Autodesk Fusion 360 part; units mm, degrees
(part 23 of 28)
  line L985 (32.9251, 30.277, -1.4859) -> (33.0999, 30.1879, -1.4859)
  line L986 (33.0999, 30.1879, -1.4859) -> (33.2586, 30.0726, -1.4859)
  line L987 (33.2586, 30.0726, -1.4859) -> (33.3973, 29.9339, -1.4859)
  line L988 (33.3973, 29.9339, -1.4859) -> (33.5126, 29.7752, -1.4859)
  line L989 (33.5126, 29.7752, -1.4859) -> (33.6016, 29.6005, -1.4859)
  line L990 (33.6016, 29.6005, -1.4859) -> (33.6622, 29.4139, -1.4859)
  line L991 (33.6622, 29.4139, -1.4859) -> (33.6929, 29.2202, -1.4859)
  line L992 (33.6929, 29.2202, -1.4859) -> (33.6968, 29.1221, -1.4859)
  line L993 (33.6968, 29.1221, -1.4859) -> (33.6968, 28.6221, -1.4859)
  line L994 (33.6968, 28.6221, -1.4859) -> (33.6929, 28.524, -1.4859)
  line L995 (33.6929, 28.524, -1.4859) -> (33.6622, 28.3303, -1.4859)
  line L996 (33.6622, 28.3303, -1.4859) -> (33.6016, 28.1438, -1.4859)
  line L997 (33.6016, 28.1438, -1.4859) -> (33.5126, 27.969, -1.4859)
  line L998 (33.5126, 27.969, -1.4859) -> (33.3973, 27.8103, -1.4859)
  line L999 (33.3973, 27.8103, -1.4859) -> (33.2586, 27.6716, -1.4859)
  line L1000 (33.2586, 27.6716, -1.4859) -> (33.0999, 27.5563, -1.4859)
  line L1001 (33.0999, 27.5563, -1.4859) -> (32.9251, 27.4673, -1.4859)
  line L1002 (32.9251, 27.4673, -1.4859) -> (32.7386, 27.4067, -1.4859)
  line L1003 (32.7386, 27.4067, -1.4859) -> (32.5448, 27.376, -1.4859)
  line L1004 (32.5448, 27.376, -1.4859) -> (32.3487, 27.376, -1.4859)
  line L1005 (32.3487, 27.376, -1.4859) -> (32.155, 27.4066, -1.4859)
  line L1006 (32.155, 27.4066, -1.4859) -> (31.9684, 27.4673, -1.4859)
  line L1007 (31.9684, 27.4673, -1.4859) -> (31.7936, 27.5563, -1.4859)
  line L1008 (31.7936, 27.5563, -1.4859) -> (31.635, 27.6716, -1.4859)
  line L1009 (31.635, 27.6716, -1.4859) -> (31.4963, 27.8103, -1.4859)
  line L1010 (31.4963, 27.8103, -1.4859) -> (31.381, 27.969, -1.4859)
  line L1011 (31.381, 27.969, -1.4859) -> (31.2919, 28.1438, -1.4859)
  line L1012 (31.2919, 28.1438, -1.4859) -> (31.2313, 28.3303, -1.4859)
  line L1013 (31.2313, 28.3303, -1.4859) -> (31.2006, 28.524, -1.4859)
  line L1014 (31.2006, 28.524, -1.4859) -> (31.1968, 28.6221, -1.4859)
  line L1015 (31.1968, 28.6221, -1.4859) -> (31.1968, 29.1221, -1.4859)
  line L1016 (31.1968, 29.1221, -1.4859) -> (31.2006, 29.2202, -1.4859)
  line L1017 (31.2006, 29.2202, -1.4859) -> (31.2313, 29.4139, -1.4859)
  line L1018 (31.2313, 29.4139, -1.4859) -> (31.2919, 29.6005, -1.4859)
  line L1019 (31.2919, 29.6005, -1.4859) -> (31.381, 29.7752, -1.4859)
  line L1020 (31.381, 29.7752, -1.4859) -> (31.4963, 29.9339, -1.4859)
  line L1021 (31.4963, 29.9339, -1.4859) -> (31.635, 30.0726, -1.4859)
  line L1022 (31.635, 30.0726, -1.4859) -> (31.7936, 30.1879, -1.4859)
  line L1023 (31.7936, 30.1879, -1.4859) -> (31.9684, 30.277, -1.4859)
  line L1024 (31.9684, 30.277, -1.4859) -> (32.155, 30.3376, -1.4859)
  line L1025 (32.155, 30.3376, -1.4859) -> (32.3487, 30.3683, -1.4859)
  line L1026 (32.3487, 30.3683, -1.4859) -> (32.5448, 30.3683, -1.4859)
  line L1027 (32.5448, 30.3683, -1.4859) -> (32.7386, 30.3376, -1.4859)
  line L1028 (93.6986, 30.3376, -1.4859) -> (93.8851, 30.277, -1.4859)
  line L1029 (93.8851, 30.277, -1.4859) -> (94.0599, 30.1879, -1.4859)
  line L1030 (94.0599, 30.1879, -1.4859) -> (94.2186, 30.0726, -1.4859)
  line L1031 (94.2186, 30.0726, -1.4859) -> (94.3573, 29.9339, -1.4859)
  line L1032 (94.3573, 29.9339, -1.4859) -> (94.4726, 29.7752, -1.4859)
  line L1033 (94.4726, 29.7752, -1.4859) -> (94.5616, 29.6005, -1.4859)
  line L1034 (94.5616, 29.6005, -1.4859) -> (94.6222, 29.4139, -1.4859)
  line L1035 (94.6222, 29.4139, -1.4859) -> (94.6529, 29.2202, -1.4859)
  line L1036 (94.6529, 29.2202, -1.4859) -> (94.6568, 29.1221, -1.4859)
  line L1037 (94.6568, 29.1221, -1.4859) -> (94.6568, 28.6221, -1.4859)
  line L1038 (94.6568, 28.6221, -1.4859) -> (94.6529, 28.524, -1.4859)
  line L1039 (94.6529, 28.524, -1.4859) -> (94.6222, 28.3303, -1.4859)
  line L1040 (94.6222, 28.3303, -1.4859) -> (94.5616, 28.1438, -1.4859)
  line L1041 (94.5616, 28.1438, -1.4859) -> (94.4726, 27.969, -1.4859)
  line L1042 (94.4726, 27.969, -1.4859) -> (94.3573, 27.8103, -1.4859)
  line L1043 (94.3573, 27.8103, -1.4859) -> (94.2186, 27.6716, -1.4859)
  line L1044 (94.2186, 27.6716, -1.4859) -> (94.0599, 27.5563, -1.4859)
  line L1045 (94.0599, 27.5563, -1.4859) -> (93.8851, 27.4673, -1.4859)
  line L1046 (93.8851, 27.4673, -1.4859) -> (93.6986, 27.4067, -1.4859)
  line L1047 (93.6986, 27.4067, -1.4859) -> (93.5048, 27.376, -1.4859)
  line L1048 (93.5048, 27.376, -1.4859) -> (93.3087, 27.376, -1.4859)
  line L1049 (93.3087, 27.376, -1.4859) -> (93.115, 27.4066, -1.4859)
  line L1050 (93.115, 27.4066, -1.4859) -> (92.9284, 27.4673, -1.4859)
  line L1051 (92.9284, 27.4673, -1.4859) -> (92.7536, 27.5563, -1.4859)
  line L1052 (92.7536, 27.5563, -1.4859) -> (92.595, 27.6716, -1.4859)
  line L1053 (92.595, 27.6716, -1.4859) -> (92.4563, 27.8103, -1.4859)
  line L1054 (92.4563, 27.8103, -1.4859) -> (92.341, 27.969, -1.4859)
  line L1055 (92.341, 27.969, -1.4859) -> (92.2519, 28.1438, -1.4859)
  line L1056 (92.2519, 28.1438, -1.4859) -> (92.1913, 28.3303, -1.4859)
  line L1057 (92.1913, 28.3303, -1.4859) -> (92.1606, 28.524, -1.4859)
  line L1058 (92.1606, 28.524, -1.4859) -> (92.1568, 28.6221, -1.4859)
  line L1059 (92.1568, 28.6221, -1.4859) -> (92.1568, 29.1221, -1.4859)
  line L1060 (92.1568, 29.1221, -1.4859) -> (92.1606, 29.2202, -1.4859)
  line L1061 (92.1606, 29.2202, -1.4859) -> (92.1913, 29.4139, -1.4859)
  line L1062 (92.1913, 29.4139, -1.4859) -> (92.2519, 29.6005, -1.4859)
  line L1063 (92.2519, 29.6005, -1.4859) -> (92.341, 29.7752, -1.4859)
  line L1064 (92.341, 29.7752, -1.4859) -> (92.4563, 29.9339, -1.4859)
  line L1065 (92.4563, 29.9339, -1.4859) -> (92.595, 30.0726, -1.4859)
  line L1066 (92.595, 30.0726, -1.4859) -> (92.7536, 30.1879, -1.4859)
  line L1067 (92.7536, 30.1879, -1.4859) -> (92.9284, 30.277, -1.4859)
  line L1068 (92.9284, 30.277, -1.4859) -> (93.115, 30.3376, -1.4859)
  line L1069 (93.115, 30.3376, -1.4859) -> (93.3087, 30.3683, -1.4859)
  line L1070 (93.3087, 30.3683, -1.4859) -> (93.5048, 30.3683, -1.4859)
  line L1071 (93.5048, 30.3683, -1.4859) -> (93.6986, 30.3376, -1.4859)
  line L1072 (22.3992, 30.1515, -1.4859) -> (22.5891, 30.1215, -1.4859)
  line L1073 (22.5891, 30.1215, -1.4859) -> (22.7719, 30.0621, -1.4859)
  line L1074 (22.7719, 30.0621, -1.4859) -> (22.9432, 29.9748, -1.4859)
  line L1075 (22.9432, 29.9748, -1.4859) -> (23.0987, 29.8618, -1.4859)
  line L1076 (23.0987, 29.8618, -1.4859) -> (23.2346, 29.7259, -1.4859)
  line L1077 (23.2346, 29.7259, -1.4859) -> (23.3476, 29.5704, -1.4859)
  line L1078 (23.3476, 29.5704, -1.4859) -> (23.4349, 29.3991, -1.4859)
  line L1079 (23.4349, 29.3991, -1.4859) -> (23.4943, 29.2163, -1.4859)
  line L1080 (23.4943, 29.2163, -1.4859) -> (23.5243, 29.0264, -1.4859)
  line L1081 (23.5243, 29.0264, -1.4859) -> (23.5243, 28.8342, -1.4859)
  line L1082 (23.5243, 28.8342, -1.4859) -> (23.4943, 28.6443, -1.4859)
  line L1083 (23.4943, 28.6443, -1.4859) -> (23.4349, 28.4615, -1.4859)
  line L1084 (23.4349, 28.4615, -1.4859) -> (23.3476, 28.2903, -1.4859)
  line L1085 (23.3476, 28.2903, -1.4859) -> (23.2346, 28.1347, -1.4859)
  line L1086 (23.2346, 28.1347, -1.4859) -> (23.0987, 27.9988, -1.4859)
  line L1087 (23.0987, 27.9988, -1.4859) -> (22.9432, 27.8858, -1.4859)
  line L1088 (22.9432, 27.8858, -1.4859) -> (22.7719, 27.7986, -1.4859)
  line L1089 (22.7719, 27.7986, -1.4859) -> (22.5891, 27.7392, -1.4859)
  line L1090 (22.5891, 27.7392, -1.4859) -> (22.3992, 27.7091, -1.4859)
  line L1091 (22.3992, 27.7091, -1.4859) -> (22.3031, 27.7053, -1.4859)
  line L1092 (22.3031, 27.7053, -1.4859) -> (21.7531, 27.7053, -1.4859)
  line L1093 (21.7531, 27.7053, -1.4859) -> (21.657, 27.7091, -1.4859)
  line L1094 (21.657, 27.7091, -1.4859) -> (21.4671, 27.7392, -1.4859)
  line L1095 (21.4671, 27.7392, -1.4859) -> (21.2843, 27.7986, -1.4859)
  line L1096 (21.2843, 27.7986, -1.4859) -> (21.1131, 27.8858, -1.4859)
  line L1097 (21.1131, 27.8858, -1.4859) -> (20.9575, 27.9988, -1.4859)
  line L1098 (20.9575, 27.9988, -1.4859) -> (20.8216, 28.1347, -1.4859)
  line L1099 (20.8216, 28.1347, -1.4859) -> (20.7086, 28.2903, -1.4859)
  line L1100 (20.7086, 28.2903, -1.4859) -> (20.6214, 28.4615, -1.4859)
  line L1101 (20.6214, 28.4615, -1.4859) -> (20.562, 28.6443, -1.4859)
  line L1102 (20.562, 28.6443, -1.4859) -> (20.5319, 28.8342, -1.4859)
  line L1103 (20.5319, 28.8342, -1.4859) -> (20.5319, 29.0264, -1.4859)
  line L1104 (20.5319, 29.0264, -1.4859) -> (20.562, 29.2163, -1.4859)
  line L1105 (20.562, 29.2163, -1.4859) -> (20.6214, 29.3991, -1.4859)
  line L1106 (20.6214, 29.3991, -1.4859) -> (20.7086, 29.5704, -1.4859)
  line L1107 (20.7086, 29.5704, -1.4859) -> (20.8216, 29.7259, -1.4859)
  line L1108 (20.8216, 29.7259, -1.4859) -> (20.9575, 29.8618, -1.4859)
  line L1109 (20.9575, 29.8618, -1.4859) -> (21.1131, 29.9748, -1.4859)
  line L1110 (21.1131, 29.9748, -1.4859) -> (21.2843, 30.0621, -1.4859)
  line L1111 (21.2843, 30.0621, -1.4859) -> (21.4671, 30.1215, -1.4859)
  line L1112 (21.4671, 30.1215, -1.4859) -> (21.657, 30.1515, -1.4859)
  line L1113 (21.657, 30.1515, -1.4859) -> (21.7531, 30.1553, -1.4859)
  line L1114 (21.7531, 30.1553, -1.4859) -> (22.3031, 30.1553, -1.4859)
  line L1115 (22.3031, 30.1553, -1.4859) -> (22.3992, 30.1515, -1.4859)
  line L1116 (83.3592, 30.1515, -1.4859) -> (83.5491, 30.1215, -1.4859)
  line L1117 (83.5491, 30.1215, -1.4859) -> (83.7319, 30.0621, -1.4859)
  line L1118 (83.7319, 30.0621, -1.4859) -> (83.9032, 29.9748, -1.4859)
  line L1119 (83.9032, 29.9748, -1.4859) -> (84.0587, 29.8618, -1.4859)
  line L1120 (84.0587, 29.8618, -1.4859) -> (84.1946, 29.7259, -1.4859)
  line L1121 (84.1946, 29.7259, -1.4859) -> (84.3076, 29.5704, -1.4859)
  line L1122 (84.3076, 29.5704, -1.4859) -> (84.3949, 29.3991, -1.4859)
  line L1123 (84.3949, 29.3991, -1.4859) -> (84.4543, 29.2163, -1.4859)
  line L1124 (84.4543, 29.2163, -1.4859) -> (84.4843, 29.0264, -1.4859)
  line L1125 (84.4843, 29.0264, -1.4859) -> (84.4843, 28.8342, -1.4859)
  line L1126 (84.4843, 28.8342, -1.4859) -> (84.4543, 28.6443, -1.4859)
  line L1127 (84.4543, 28.6443, -1.4859) -> (84.3949, 28.4615, -1.4859)
  line L1128 (84.3949, 28.4615, -1.4859) -> (84.3076, 28.2903, -1.4859)
  line L1129 (84.3076, 28.2903, -1.4859) -> (84.1946, 28.1347, -1.4859)
  line L1130 (84.1946, 28.1347, -1.4859) -> (84.0587, 27.9988, -1.4859)
  line L1131 (84.0587, 27.9988, -1.4859) -> (83.9032, 27.8858, -1.4859)
  line L1132 (83.9032, 27.8858, -1.4859) -> (83.7319, 27.7986, -1.4859)
  line L1133 (83.7319, 27.7986, -1.4859) -> (83.5491, 27.7392, -1.4859)
  line L1134 (83.5491, 27.7392, -1.4859) -> (83.3592, 27.7091, -1.4859)
  line L1135 (83.3592, 27.7091, -1.4859) -> (83.2631, 27.7053, -1.4859)
  line L1136 (83.2631, 27.7053, -1.4859) -> (82.7131, 27.7053, -1.4859)
  line L1137 (82.7131, 27.7053, -1.4859) -> (82.617, 27.7091, -1.4859)
  line L1138 (82.617, 27.7091, -1.4859) -> (82.4271, 27.7392, -1.4859)
  line L1139 (82.4271, 27.7392, -1.4859) -> (82.2443, 27.7986, -1.4859)
  line L1140 (82.2443, 27.7986, -1.4859) -> (82.0731, 27.8858, -1.4859)
  line L1141 (82.0731, 27.8858, -1.4859) -> (81.9175, 27.9988, -1.4859)
  line L1142 (81.9175, 27.9988, -1.4859) -> (81.7816, 28.1347, -1.4859)
  line L1143 (81.7816, 28.1347, -1.4859) -> (81.6686, 28.2903, -1.4859)
  line L1144 (81.6686, 28.2903, -1.4859) -> (81.5814, 28.4615, -1.4859)
  line L1145 (81.5814, 28.4615, -1.4859) -> (81.522, 28.6443, -1.4859)
  line L1146 (81.522, 28.6443, -1.4859) -> (81.4919, 28.8342, -1.4859)
  line L1147 (81.4919, 28.8342, -1.4859) -> (81.4919, 29.0264, -1.4859)
  line L1148 (81.4919, 29.0264, -1.4859) -> (81.522, 29.2163, -1.4859)
  line L1149 (81.522, 29.2163, -1.4859) -> (81.5814, 29.3991, -1.4859)
  line L1150 (81.5814, 29.3991, -1.4859) -> (81.6686, 29.5704, -1.4859)
  line L1151 (81.6686, 29.5704, -1.4859) -> (81.7816, 29.7259, -1.4859)
  line L1152 (81.7816, 29.7259, -1.4859) -> (81.9175, 29.8618, -1.4859)
  line L1153 (81.9175, 29.8618, -1.4859) -> (82.0731, 29.9748, -1.4859)
  line L1154 (82.0731, 29.9748, -1.4859) -> (82.2443, 30.0621, -1.4859)
  line L1155 (82.2443, 30.0621, -1.4859) -> (82.4271, 30.1215, -1.4859)
  line L1156 (82.4271, 30.1215, -1.4859) -> (82.617, 30.1515, -1.4859)
  line L1157 (82.617, 30.1515, -1.4859) -> (82.7131, 30.1553, -1.4859)
  line L1158 (82.7131, 30.1553, -1.4859) -> (83.2631, 30.1553, -1.4859)
  line L1159 (83.2631, 30.1553, -1.4859) -> (83.3592, 30.1515, -1.4859)
  line L1160 (12.0738, 27.7692, -1.4859) -> (9.0738, 27.7692, -1.4859)
  line L1161 (9.0738, 27.7692, -1.4859) -> (9.0738, 30.2192, -1.4859)
  line L1162 (9.0738, 30.2192, -1.4859) -> (12.0738, 30.2192, -1.4859)
  line L1163 (12.0738, 30.2192, -1.4859) -> (12.0738, 27.7692, -1.4859)
  line L1164 (73.0338, 27.7692, -1.4859) -> (70.0338, 27.7692, -1.4859)
  line L1165 (70.0338, 27.7692, -1.4859) -> (70.0338, 30.2192, -1.4859)
  line L1166 (70.0338, 30.2192, -1.4859) -> (73.0338, 30.2192, -1.4859)
  line L1167 (73.0338, 30.2192, -1.4859) -> (73.0338, 27.7692, -1.4859)
  line L1168 (43.8715, 29.8787, -1.4859) -> (44.0638, 29.8404, -1.4859)
  line L1169 (44.0638, 29.8404, -1.4859) -> (44.2449, 29.7654, -1.4859)
  line L1170 (44.2449, 29.7654, -1.4859) -> (44.4079, 29.6565, -1.4859)
  line L1171 (44.4079, 29.6565, -1.4859) -> (44.5465, 29.5179, -1.4859)
  line L1172 (44.5465, 29.5179, -1.4859) -> (44.6554, 29.3549, -1.4859)
  line L1173 (44.6554, 29.3549, -1.4859) -> (44.7304, 29.1738, -1.4859)
  line L1174 (44.7304, 29.1738, -1.4859) -> (44.7687, 28.9815, -1.4859)
  line L1175 (44.7687, 28.9815, -1.4859) -> (44.7687, 28.7855, -1.4859)
  line L1176 (44.7687, 28.7855, -1.4859) -> (44.7304, 28.5932, -1.4859)
  line L1177 (44.7304, 28.5932, -1.4859) -> (44.6554, 28.4121, -1.4859)
  line L1178 (44.6554, 28.4121, -1.4859) -> (44.5465, 28.2491, -1.4859)
  line L1179 (44.5465, 28.2491, -1.4859) -> (44.4079, 28.1105, -1.4859)
  line L1180 (44.4079, 28.1105, -1.4859) -> (44.2449, 28.0016, -1.4859)
  line L1181 (44.2449, 28.0016, -1.4859) -> (44.0638, 27.9265, -1.4859)
  line L1182 (44.0638, 27.9265, -1.4859) -> (43.8715, 27.8883, -1.4859)
  line L1183 (43.8715, 27.8883, -1.4859) -> (43.7735, 27.8835, -1.4859)
  line L1184 (43.7735, 27.8835, -1.4859) -> (42.5735, 27.8835, -1.4859)
  line L1185 (42.5735, 27.8835, -1.4859) -> (42.4755, 27.8883, -1.4859)
  line L1186 (42.4755, 27.8883, -1.4859) -> (42.2832, 27.9265, -1.4859)
  line L1187 (42.2832, 27.9265, -1.4859) -> (42.1021, 28.0016, -1.4859)
  line L1188 (42.1021, 28.0016, -1.4859) -> (41.9391, 28.1105, -1.4859)
  line L1189 (41.9391, 28.1105, -1.4859) -> (41.8005, 28.2491, -1.4859)
  line L1190 (41.8005, 28.2491, -1.4859) -> (41.6916, 28.4121, -1.4859)
  line L1191 (41.6916, 28.4121, -1.4859) -> (41.6165, 28.5932, -1.4859)
  line L1192 (41.6165, 28.5932, -1.4859) -> (41.5783, 28.7855, -1.4859)
  line L1193 (41.5783, 28.7855, -1.4859) -> (41.5783, 28.9815, -1.4859)
  line L1194 (41.5783, 28.9815, -1.4859) -> (41.6165, 29.1738, -1.4859)
  line L1195 (41.6165, 29.1738, -1.4859) -> (41.6916, 29.3549, -1.4859)
  line L1196 (41.6916, 29.3549, -1.4859) -> (41.8005, 29.5179, -1.4859)
  line L1197 (41.8005, 29.5179, -1.4859) -> (41.9391, 29.6565, -1.4859)
  line L1198 (41.9391, 29.6565, -1.4859) -> (42.1021, 29.7654, -1.4859)
  line L1199 (42.1021, 29.7654, -1.4859) -> (42.2832, 29.8404, -1.4859)
  line L1200 (42.2832, 29.8404, -1.4859) -> (42.4755, 29.8787, -1.4859)
  line L1201 (42.4755, 29.8787, -1.4859) -> (42.5735, 29.8835, -1.4859)
  line L1202 (42.5735, 29.8835, -1.4859) -> (43.7735, 29.8835, -1.4859)
  line L1203 (43.7735, 29.8835, -1.4859) -> (43.8715, 29.8787, -1.4859)
  line L1204 (104.8315, 29.8787, -1.4859) -> (105.0238, 29.8404, -1.4859)
  line L1205 (105.0238, 29.8404, -1.4859) -> (105.2049, 29.7654, -1.4859)
  line L1206 (105.2049, 29.7654, -1.4859) -> (105.3679, 29.6565, -1.4859)
  line L1207 (105.3679, 29.6565, -1.4859) -> (105.5065, 29.5179, -1.4859)
  line L1208 (105.5065, 29.5179, -1.4859) -> (105.6154, 29.3549, -1.4859)
  line L1209 (105.6154, 29.3549, -1.4859) -> (105.6904, 29.1738, -1.4859)
  line L1210 (105.6904, 29.1738, -1.4859) -> (105.7287, 28.9815, -1.4859)
  line L1211 (105.7287, 28.9815, -1.4859) -> (105.7287, 28.7855, -1.4859)
  line L1212 (105.7287, 28.7855, -1.4859) -> (105.6904, 28.5932, -1.4859)
  line L1213 (105.6904, 28.5932, -1.4859) -> (105.6154, 28.4121, -1.4859)
  line L1214 (105.6154, 28.4121, -1.4859) -> (105.5065, 28.2491, -1.4859)
  line L1215 (105.5065, 28.2491, -1.4859) -> (105.3679, 28.1105, -1.4859)
  line L1216 (105.3679, 28.1105, -1.4859) -> (105.2049, 28.0016, -1.4859)
  line L1217 (105.2049, 28.0016, -1.4859) -> (105.0238, 27.9265, -1.4859)
  line L1218 (105.0238, 27.9265, -1.4859) -> (104.8315, 27.8883, -1.4859)
  line L1219 (104.8315, 27.8883, -1.4859) -> (104.7335, 27.8835, -1.4859)
  line L1220 (104.7335, 27.8835, -1.4859) -> (103.5335, 27.8835, -1.4859)
  line L1221 (103.5335, 27.8835, -1.4859) -> (103.4355, 27.8883, -1.4859)
  line L1222 (103.4355, 27.8883, -1.4859) -> (103.2432, 27.9265, -1.4859)
  line L1223 (103.2432, 27.9265, -1.4859) -> (103.0621, 28.0016, -1.4859)
  line L1224 (103.0621, 28.0016, -1.4859) -> (102.8991, 28.1105, -1.4859)
  line L1225 (102.8991, 28.1105, -1.4859) -> (102.7605, 28.2491, -1.4859)
  line L1226 (102.7605, 28.2491, -1.4859) -> (102.6516, 28.4121, -1.4859)
  line L1227 (102.6516, 28.4121, -1.4859) -> (102.5765, 28.5932, -1.4859)
  line L1228 (102.5765, 28.5932, -1.4859) -> (102.5383, 28.7855, -1.4859)
  line L1229 (102.5383, 28.7855, -1.4859) -> (102.5383, 28.9815, -1.4859)
  line L1230 (102.5383, 28.9815, -1.4859) -> (102.5765, 29.1738, -1.4859)
  line L1231 (102.5765, 29.1738, -1.4859) -> (102.6516, 29.3549, -1.4859)
  line L1232 (102.6516, 29.3549, -1.4859) -> (102.7605, 29.5179, -1.4859)
  line L1233 (102.7605, 29.5179, -1.4859) -> (102.8991, 29.6565, -1.4859)
  line L1234 (102.8991, 29.6565, -1.4859) -> (103.0621, 29.7654, -1.4859)
  line L1235 (103.0621, 29.7654, -1.4859) -> (103.2432, 29.8404, -1.4859)
  line L1236 (103.2432, 29.8404, -1.4859) -> (103.4355, 29.8787, -1.4859)
  line L1237 (103.4355, 29.8787, -1.4859) -> (103.5335, 29.8835, -1.4859)
  line L1238 (103.5335, 29.8835, -1.4859) -> (104.7335, 29.8835, -1.4859)
  line L1239 (104.7335, 29.8835, -1.4859) -> (104.8315, 29.8787, -1.4859)
  line L1240 (50.1588, 32.3813, -1.4859) -> (50.3454, 32.3207, -1.4859)
  line L1241 (50.3454, 32.3207, -1.4859) -> (50.5202, 32.2316, -1.4859)
  line L1242 (50.5202, 32.2316, -1.4859) -> (50.6788, 32.1163, -1.4859)
  line L1243 (50.6788, 32.1163, -1.4859) -> (50.8175, 31.9776, -1.4859)
  line L1244 (50.8175, 31.9776, -1.4859) -> (50.9328, 31.8189, -1.4859)
  line L1245 (50.9328, 31.8189, -1.4859) -> (51.0219, 31.6442, -1.4859)
  line L1246 (51.0219, 31.6442, -1.4859) -> (51.0825, 31.4576, -1.4859)
  line L1247 (51.0825, 31.4576, -1.4859) -> (51.1132, 31.2639, -1.4859)
  line L1248 (51.1132, 31.2639, -1.4859) -> (51.117, 31.1658, -1.4859)
  line L1249 (51.117, 31.1658, -1.4859) -> (51.117, 30.6658, -1.4859)
  line L1250 (51.117, 30.6658, -1.4859) -> (51.1132, 30.5677, -1.4859)
  line L1251 (51.1132, 30.5677, -1.4859) -> (51.0825, 30.374, -1.4859)
  line L1252 (51.0825, 30.374, -1.4859) -> (51.0219, 30.1875, -1.4859)
  line L1253 (51.0219, 30.1875, -1.4859) -> (50.9328, 30.0127, -1.4859)
  line L1254 (50.9328, 30.0127, -1.4859) -> (50.8175, 29.854, -1.4859)
  line L1255 (50.8175, 29.854, -1.4859) -> (50.6788, 29.7153, -1.4859)
  line L1256 (50.6788, 29.7153, -1.4859) -> (50.5202, 29.6, -1.4859)
  line L1257 (50.5202, 29.6, -1.4859) -> (50.3454, 29.511, -1.4859)
  line L1258 (50.3454, 29.511, -1.4859) -> (50.1588, 29.4504, -1.4859)
  line L1259 (50.1588, 29.4504, -1.4859) -> (49.9651, 29.4197, -1.4859)
  line L1260 (49.9651, 29.4197, -1.4859) -> (49.769, 29.4197, -1.4859)
  line L1261 (49.769, 29.4197, -1.4859) -> (49.5752, 29.4504, -1.4859)
  line L1262 (49.5752, 29.4504, -1.4859) -> (49.3887, 29.511, -1.4859)
  line L1263 (49.3887, 29.511, -1.4859) -> (49.2139, 29.6, -1.4859)
  line L1264 (49.2139, 29.6, -1.4859) -> (49.0552, 29.7153, -1.4859)
  line L1265 (49.0552, 29.7153, -1.4859) -> (48.9165, 29.854, -1.4859)
  line L1266 (48.9165, 29.854, -1.4859) -> (48.8012, 30.0127, -1.4859)
  line L1267 (48.8012, 30.0127, -1.4859) -> (48.7122, 30.1875, -1.4859)
  line L1268 (48.7122, 30.1875, -1.4859) -> (48.6516, 30.374, -1.4859)
  line L1269 (48.6516, 30.374, -1.4859) -> (48.6209, 30.5677, -1.4859)
  line L1270 (48.6209, 30.5677, -1.4859) -> (48.617, 30.6658, -1.4859)
  line L1271 (48.617, 30.6658, -1.4859) -> (48.617, 31.1658, -1.4859)
  line L1272 (48.617, 31.1658, -1.4859) -> (48.6209, 31.2639, -1.4859)
  line L1273 (48.6209, 31.2639, -1.4859) -> (48.6516, 31.4576, -1.4859)
  line L1274 (48.6516, 31.4576, -1.4859) -> (48.7122, 31.6442, -1.4859)
  line L1275 (48.7122, 31.6442, -1.4859) -> (48.8012, 31.8189, -1.4859)
  line L1276 (48.8012, 31.8189, -1.4859) -> (48.9165, 31.9776, -1.4859)
  line L1277 (48.9165, 31.9776, -1.4859) -> (49.0552, 32.1163, -1.4859)
  line L1278 (49.0552, 32.1163, -1.4859) -> (49.2139, 32.2316, -1.4859)
  line L1279 (49.2139, 32.2316, -1.4859) -> (49.3887, 32.3207, -1.4859)
  line L1280 (49.3887, 32.3207, -1.4859) -> (49.5752, 32.3813, -1.4859)
  line L1281 (49.5752, 32.3813, -1.4859) -> (49.769, 32.412, -1.4859)
  line L1282 (49.769, 32.412, -1.4859) -> (49.9651, 32.412, -1.4859)
  line L1283 (49.9651, 32.412, -1.4859) -> (50.1588, 32.3813, -1.4859)
  line L1284 (111.1188, 32.3813, -1.4859) -> (111.3054, 32.3207, -1.4859)
  line L1285 (111.3054, 32.3207, -1.4859) -> (111.4802, 32.2316, -1.4859)
  line L1286 (111.4802, 32.2316, -1.4859) -> (111.6388, 32.1163, -1.4859)
  line L1287 (111.6388, 32.1163, -1.4859) -> (111.7775, 31.9776, -1.4859)
  line L1288 (111.7775, 31.9776, -1.4859) -> (111.8928, 31.8189, -1.4859)
  line L1289 (111.8928, 31.8189, -1.4859) -> (111.9819, 31.6442, -1.4859)
  line L1290 (111.9819, 31.6442, -1.4859) -> (112.0425, 31.4576, -1.4859)
  line L1291 (112.0425, 31.4576, -1.4859) -> (112.0732, 31.2639, -1.4859)
  line L1292 (112.0732, 31.2639, -1.4859) -> (112.077, 31.1658, -1.4859)
  line L1293 (112.077, 31.1658, -1.4859) -> (112.077, 30.6658, -1.4859)
  line L1294 (112.077, 30.6658, -1.4859) -> (112.0732, 30.5677, -1.4859)
  line L1295 (112.0732, 30.5677, -1.4859) -> (112.0425, 30.374, -1.4859)
  line L1296 (112.0425, 30.374, -1.4859) -> (111.9819, 30.1875, -1.4859)
  line L1297 (111.9819, 30.1875, -1.4859) -> (111.8928, 30.0127, -1.4859)
  line L1298 (111.8928, 30.0127, -1.4859) -> (111.7775, 29.854, -1.4859)
  line L1299 (111.7775, 29.854, -1.4859) -> (111.6388, 29.7153, -1.4859)
  line L1300 (111.6388, 29.7153, -1.4859) -> (111.4802, 29.6, -1.4859)
  line L1301 (111.4802, 29.6, -1.4859) -> (111.3054, 29.511, -1.4859)
  line L1302 (111.3054, 29.511, -1.4859) -> (111.1188, 29.4504, -1.4859)
  line L1303 (111.1188, 29.4504, -1.4859) -> (110.9251, 29.4197, -1.4859)
  line L1304 (110.9251, 29.4197, -1.4859) -> (110.729, 29.4197, -1.4859)
  line L1305 (110.729, 29.4197, -1.4859) -> (110.5352, 29.4504, -1.4859)
  line L1306 (110.5352, 29.4504, -1.4859) -> (110.3487, 29.511, -1.4859)
  line L1307 (110.3487, 29.511, -1.4859) -> (110.1739, 29.6, -1.4859)
  line L1308 (110.1739, 29.6, -1.4859) -> (110.0152, 29.7153, -1.4859)
  line L1309 (110.0152, 29.7153, -1.4859) -> (109.8765, 29.854, -1.4859)
  line L1310 (109.8765, 29.854, -1.4859) -> (109.7612, 30.0127, -1.4859)
  line L1311 (109.7612, 30.0127, -1.4859) -> (109.6722, 30.1875, -1.4859)
  line L1312 (109.6722, 30.1875, -1.4859) -> (109.6116, 30.374, -1.4859)
  line L1313 (109.6116, 30.374, -1.4859) -> (109.5809, 30.5677, -1.4859)
  line L1314 (109.5809, 30.5677, -1.4859) -> (109.577, 30.6658, -1.4859)
  line L1315 (109.577, 30.6658, -1.4859) -> (109.577, 31.1658, -1.4859)
  line L1316 (109.577, 31.1658, -1.4859) -> (109.5809, 31.2639, -1.4859)
  line L1317 (109.5809, 31.2639, -1.4859) -> (109.6116, 31.4576, -1.4859)
  line L1318 (109.6116, 31.4576, -1.4859) -> (109.6722, 31.6442, -1.4859)
  line L1319 (109.6722, 31.6442, -1.4859) -> (109.7612, 31.8189, -1.4859)
  line L1320 (109.7612, 31.8189, -1.4859) -> (109.8765, 31.9776, -1.4859)
  line L1321 (109.8765, 31.9776, -1.4859) -> (110.0152, 32.1163, -1.4859)
  line L1322 (110.0152, 32.1163, -1.4859) -> (110.1739, 32.2316, -1.4859)
  line L1323 (110.1739, 32.2316, -1.4859) -> (110.3487, 32.3207, -1.4859)
  line L1324 (110.3487, 32.3207, -1.4859) -> (110.5352, 32.3813, -1.4859)
  line L1325 (110.5352, 32.3813, -1.4859) -> (110.729, 32.412, -1.4859)
  line L1326 (110.729, 32.412, -1.4859) -> (110.9251, 32.412, -1.4859)
  line L1327 (110.9251, 32.412, -1.4859) -> (111.1188, 32.3813, -1.4859)
  line L1328 (23.2545, 32.6394, -1.4859) -> (23.3677, 32.5841, -1.4859)
  line L1329 (23.3677, 32.5841, -1.4859) -> (23.4569, 32.4949, -1.4859)
  line L1330 (23.4569, 32.4949, -1.4859) -> (23.5122, 32.3817, -1.4859)
  line L1331 (23.5122, 32.3817, -1.4859) -> (23.5281, 32.2725, -1.4859)
  line L1332 (23.5281, 32.2725, -1.4859) -> (23.5281, 30.5881, -1.4859)
  line L1333 (23.5281, 30.5881, -1.4859) -> (23.5122, 30.4789, -1.4859)
  line L1334 (23.5122, 30.4789, -1.4859) -> (23.4569, 30.3657, -1.4859)
  line L1335 (23.4569, 30.3657, -1.4859) -> (23.3677, 30.2766, -1.4859)
  line L1336 (23.3677, 30.2766, -1.4859) -> (23.2545, 30.2212, -1.4859)
  line L1337 (23.2545, 30.2212, -1.4859) -> (23.1453, 30.2053, -1.4859)
  line L1338 (23.1453, 30.2053, -1.4859) -> (20.9109, 30.2053, -1.4859)
  line L1339 (20.9109, 30.2053, -1.4859) -> (20.8017, 30.2212, -1.4859)
  line L1340 (20.8017, 30.2212, -1.4859) -> (20.6885, 30.2766, -1.4859)
  line L1341 (20.6885, 30.2766, -1.4859) -> (20.5994, 30.3657, -1.4859)
  line L1342 (20.5994, 30.3657, -1.4859) -> (20.544, 30.4789, -1.4859)
  line L1343 (20.544, 30.4789, -1.4859) -> (20.5281, 30.5881, -1.4859)
  line L1344 (20.5281, 30.5881, -1.4859) -> (20.5281, 32.2725, -1.4859)
  line L1345 (20.5281, 32.2725, -1.4859) -> (20.544, 32.3817, -1.4859)
  line L1346 (20.544, 32.3817, -1.4859) -> (20.5994, 32.4949, -1.4859)
  line L1347 (20.5994, 32.4949, -1.4859) -> (20.6885, 32.5841, -1.4859)
  line L1348 (20.6885, 32.5841, -1.4859) -> (20.8017, 32.6394, -1.4859)
  line L1349 (20.8017, 32.6394, -1.4859) -> (20.9109, 32.6553, -1.4859)
  line L1350 (20.9109, 32.6553, -1.4859) -> (23.1453, 32.6553, -1.4859)
  line L1351 (23.1453, 32.6553, -1.4859) -> (23.2545, 32.6394, -1.4859)
  line L1352 (84.2145, 32.6394, -1.4859) -> (84.3277, 32.5841, -1.4859)
  line L1353 (84.3277, 32.5841, -1.4859) -> (84.4169, 32.4949, -1.4859)
  line L1354 (84.4169, 32.4949, -1.4859) -> (84.4722, 32.3817, -1.4859)
  line L1355 (84.4722, 32.3817, -1.4859) -> (84.4881, 32.2725, -1.4859)
  line L1356 (84.4881, 32.2725, -1.4859) -> (84.4881, 30.5881, -1.4859)
  line L1357 (84.4881, 30.5881, -1.4859) -> (84.4722, 30.4789, -1.4859)
  line L1358 (84.4722, 30.4789, -1.4859) -> (84.4169, 30.3657, -1.4859)
  line L1359 (84.4169, 30.3657, -1.4859) -> (84.3277, 30.2766, -1.4859)
  line L1360 (84.3277, 30.2766, -1.4859) -> (84.2145, 30.2212, -1.4859)
  line L1361 (84.2145, 30.2212, -1.4859) -> (84.1053, 30.2053, -1.4859)
  line L1362 (84.1053, 30.2053, -1.4859) -> (81.8709, 30.2053, -1.4859)
  line L1363 (81.8709, 30.2053, -1.4859) -> (81.7617, 30.2212, -1.4859)
  line L1364 (81.7617, 30.2212, -1.4859) -> (81.6485, 30.2766, -1.4859)
  line L1365 (81.6485, 30.2766, -1.4859) -> (81.5594, 30.3657, -1.4859)
  line L1366 (81.5594, 30.3657, -1.4859) -> (81.504, 30.4789, -1.4859)
  line L1367 (81.504, 30.4789, -1.4859) -> (81.4881, 30.5881, -1.4859)
  line L1368 (81.4881, 30.5881, -1.4859) -> (81.4881, 32.2725, -1.4859)
  line L1369 (81.4881, 32.2725, -1.4859) -> (81.504, 32.3817, -1.4859)
  line L1370 (81.504, 32.3817, -1.4859) -> (81.5594, 32.4949, -1.4859)
  line L1371 (81.5594, 32.4949, -1.4859) -> (81.6485, 32.5841, -1.4859)
  line L1372 (81.6485, 32.5841, -1.4859) -> (81.7617, 32.6394, -1.4859)
  line L1373 (81.7617, 32.6394, -1.4859) -> (81.8709, 32.6553, -1.4859)
  line L1374 (81.8709, 32.6553, -1.4859) -> (84.1053, 32.6553, -1.4859)
  line L1375 (84.1053, 32.6553, -1.4859) -> (84.2145, 32.6394, -1.4859)
  line L1376 (10.9449, 32.7554, -1.4859) -> (11.1348, 32.7254, -1.4859)
  line L1377 (11.1348, 32.7254, -1.4859) -> (11.3176, 32.666, -1.4859)
  line L1378 (11.3176, 32.666, -1.4859) -> (11.4889, 32.5787, -1.4859)
  line L1379 (11.4889, 32.5787, -1.4859) -> (11.6444, 32.4657, -1.4859)
  line L1380 (11.6444, 32.4657, -1.4859) -> (11.7803, 32.3298, -1.4859)
  line L1381 (11.7803, 32.3298, -1.4859) -> (11.8933, 32.1743, -1.4859)
  line L1382 (11.8933, 32.1743, -1.4859) -> (11.9806, 32.003, -1.4859)
  line L1383 (11.9806, 32.003, -1.4859) -> (12.04, 31.8202, -1.4859)
  line L1384 (12.04, 31.8202, -1.4859) -> (12.0701, 31.6303, -1.4859)
  line L1385 (12.0701, 31.6303, -1.4859) -> (12.0701, 31.4381, -1.4859)
  line L1386 (12.0701, 31.4381, -1.4859) -> (12.04, 31.2482, -1.4859)
  line L1387 (12.04, 31.2482, -1.4859) -> (11.9806, 31.0654, -1.4859)
  line L1388 (11.9806, 31.0654, -1.4859) -> (11.8933, 30.8941, -1.4859)
  line L1389 (11.8933, 30.8941, -1.4859) -> (11.7803, 30.7386, -1.4859)
  line L1390 (11.7803, 30.7386, -1.4859) -> (11.6444, 30.6027, -1.4859)
  line L1391 (11.6444, 30.6027, -1.4859) -> (11.4889, 30.4897, -1.4859)
  line L1392 (11.4889, 30.4897, -1.4859) -> (11.3176, 30.4024, -1.4859)
  line L1393 (11.3176, 30.4024, -1.4859) -> (11.1348, 30.343, -1.4859)
  line L1394 (11.1348, 30.343, -1.4859) -> (10.9449, 30.313, -1.4859)
  line L1395 (10.9449, 30.313, -1.4859) -> (10.8488, 30.3092, -1.4859)
  line L1396 (10.8488, 30.3092, -1.4859) -> (10.2988, 30.3092, -1.4859)
  line L1397 (10.2988, 30.3092, -1.4859) -> (10.2027, 30.313, -1.4859)
  line L1398 (10.2027, 30.313, -1.4859) -> (10.0129, 30.343, -1.4859)
  line L1399 (10.0129, 30.343, -1.4859) -> (9.8301, 30.4024, -1.4859)
  line L1400 (9.8301, 30.4024, -1.4859) -> (9.6588, 30.4897, -1.4859)
  line L1401 (9.6588, 30.4897, -1.4859) -> (9.5033, 30.6027, -1.4859)
  line L1402 (9.5033, 30.6027, -1.4859) -> (9.3673, 30.7386, -1.4859)
  line L1403 (9.3673, 30.7386, -1.4859) -> (9.2544, 30.8941, -1.4859)
  line L1404 (9.2544, 30.8941, -1.4859) -> (9.1671, 31.0654, -1.4859)
  line L1405 (9.1671, 31.0654, -1.4859) -> (9.1077, 31.2482, -1.4859)
  line L1406 (9.1077, 31.2482, -1.4859) -> (9.0776, 31.4381, -1.4859)
  line L1407 (9.0776, 31.4381, -1.4859) -> (9.0776, 31.6303, -1.4859)
  line L1408 (9.0776, 31.6303, -1.4859) -> (9.1077, 31.8202, -1.4859)
  line L1409 (9.1077, 31.8202, -1.4859) -> (9.1671, 32.003, -1.4859)
  line L1410 (9.1671, 32.003, -1.4859) -> (9.2544, 32.1743, -1.4859)
  line L1411 (9.2544, 32.1743, -1.4859) -> (9.3673, 32.3298, -1.4859)
  line L1412 (9.3673, 32.3298, -1.4859) -> (9.5033, 32.4657, -1.4859)
  line L1413 (9.5033, 32.4657, -1.4859) -> (9.6588, 32.5787, -1.4859)
  line L1414 (9.6588, 32.5787, -1.4859) -> (9.8301, 32.666, -1.4859)
  line L1415 (9.8301, 32.666, -1.4859) -> (10.0129, 32.7254, -1.4859)
  line L1416 (10.0129, 32.7254, -1.4859) -> (10.2027, 32.7554, -1.4859)
  line L1417 (10.2027, 32.7554, -1.4859) -> (10.2988, 32.7592, -1.4859)
  line L1418 (10.2988, 32.7592, -1.4859) -> (10.8488, 32.7592, -1.4859)
  line L1419 (10.8488, 32.7592, -1.4859) -> (10.9449, 32.7554, -1.4859)
  line L1420 (71.9049, 32.7554, -1.4859) -> (72.0948, 32.7254, -1.4859)
  line L1421 (72.0948, 32.7254, -1.4859) -> (72.2776, 32.666, -1.4859)
  line L1422 (72.2776, 32.666, -1.4859) -> (72.4489, 32.5787, -1.4859)
  line L1423 (72.4489, 32.5787, -1.4859) -> (72.6044, 32.4657, -1.4859)
  line L1424 (72.6044, 32.4657, -1.4859) -> (72.7403, 32.3298, -1.4859)
  line L1425 (72.7403, 32.3298, -1.4859) -> (72.8533, 32.1743, -1.4859)
  line L1426 (72.8533, 32.1743, -1.4859) -> (72.9406, 32.003, -1.4859)
  line L1427 (72.9406, 32.003, -1.4859) -> (73, 31.8202, -1.4859)
  line L1428 (73, 31.8202, -1.4859) -> (73.0301, 31.6303, -1.4859)
  line L1429 (73.0301, 31.6303, -1.4859) -> (73.0301, 31.4381, -1.4859)
  line L1430 (73.0301, 31.4381, -1.4859) -> (73, 31.2482, -1.4859)
  line L1431 (73, 31.2482, -1.4859) -> (72.9406, 31.0654, -1.4859)
  line L1432 (72.9406, 31.0654, -1.4859) -> (72.8533, 30.8941, -1.4859)
  line L1433 (72.8533, 30.8941, -1.4859) -> (72.7403, 30.7386, -1.4859)
  line L1434 (72.7403, 30.7386, -1.4859) -> (72.6044, 30.6027, -1.4859)
  line L1435 (72.6044, 30.6027, -1.4859) -> (72.4489, 30.4897, -1.4859)
  line L1436 (72.4489, 30.4897, -1.4859) -> (72.2776, 30.4024, -1.4859)
  line L1437 (72.2776, 30.4024, -1.4859) -> (72.0948, 30.343, -1.4859)
  line L1438 (72.0948, 30.343, -1.4859) -> (71.9049, 30.313, -1.4859)
  line L1439 (71.9049, 30.313, -1.4859) -> (71.8088, 30.3092, -1.4859)
  line L1440 (71.8088, 30.3092, -1.4859) -> (71.2588, 30.3092, -1.4859)
  line L1441 (71.2588, 30.3092, -1.4859) -> (71.1627, 30.313, -1.4859)
  line L1442 (71.1627, 30.313, -1.4859) -> (70.9729, 30.343, -1.4859)
  line L1443 (70.9729, 30.343, -1.4859) -> (70.7901, 30.4024, -1.4859)
  line L1444 (70.7901, 30.4024, -1.4859) -> (70.6188, 30.4897, -1.4859)
  line L1445 (70.6188, 30.4897, -1.4859) -> (70.4633, 30.6027, -1.4859)
  line L1446 (70.4633, 30.6027, -1.4859) -> (70.3273, 30.7386, -1.4859)
  line L1447 (70.3273, 30.7386, -1.4859) -> (70.2144, 30.8941, -1.4859)
  line L1448 (70.2144, 30.8941, -1.4859) -> (70.1271, 31.0654, -1.4859)
  line L1449 (70.1271, 31.0654, -1.4859) -> (70.0677, 31.2482, -1.4859)
  line L1450 (70.0677, 31.2482, -1.4859) -> (70.0376, 31.4381, -1.4859)
  line L1451 (70.0376, 31.4381, -1.4859) -> (70.0376, 31.6303, -1.4859)
  line L1452 (70.0376, 31.6303, -1.4859) -> (70.0677, 31.8202, -1.4859)
  line L1453 (70.0677, 31.8202, -1.4859) -> (70.1271, 32.003, -1.4859)
  line L1454 (70.1271, 32.003, -1.4859) -> (70.2144, 32.1743, -1.4859)
  line L1455 (70.2144, 32.1743, -1.4859) -> (70.3273, 32.3298, -1.4859)
  line L1456 (70.3273, 32.3298, -1.4859) -> (70.4633, 32.4657, -1.4859)
  line L1457 (70.4633, 32.4657, -1.4859) -> (70.6188, 32.5787, -1.4859)
  line L1458 (70.6188, 32.5787, -1.4859) -> (70.7901, 32.666, -1.4859)
  line L1459 (70.7901, 32.666, -1.4859) -> (70.9729, 32.7254, -1.4859)
  line L1460 (70.9729, 32.7254, -1.4859) -> (71.1627, 32.7554, -1.4859)
  line L1461 (71.1627, 32.7554, -1.4859) -> (71.2588, 32.7592, -1.4859)
  line L1462 (71.2588, 32.7592, -1.4859) -> (71.8088, 32.7592, -1.4859)
  line L1463 (71.8088, 32.7592, -1.4859) -> (71.9049, 32.7554, -1.4859)
  line L1464 (44.7735, 30.6535, -1.4859) -> (41.5735, 30.6535, -1.4859)
  line L1465 (41.5735, 30.6535, -1.4859) -> (41.5735, 32.6535, -1.4859)
  line L1466 (41.5735, 32.6535, -1.4859) -> (44.7735, 32.6535, -1.4859)
  line L1467 (44.7735, 32.6535, -1.4859) -> (44.7735, 30.6535, -1.4859)
  line L1468 (105.7335, 30.6535, -1.4859) -> (102.5335, 30.6535, -1.4859)
  line L1469 (102.5335, 30.6535, -1.4859) -> (102.5335, 32.6535, -1.4859)
  line L1470 (102.5335, 32.6535, -1.4859) -> (105.7335, 32.6535, -1.4859)
  line L1471 (105.7335, 32.6535, -1.4859) -> (105.7335, 30.6535, -1.4859)
  line L1472 (17.3158, 40.7738, -1.4859) -> (14.8658, 40.7738, -1.4859)
  line L1473 (14.8658, 40.7738, -1.4859) -> (14.8658, 43.7738, -1.4859)
  line L1474 (14.8658, 43.7738, -1.4859) -> (17.3158, 43.7738, -1.4859)
  line L1475 (17.3158, 43.7738, -1.4859) -> (17.3158, 40.7738, -1.4859)
  line L1476 (52.2408, 40.7738, -1.4859) -> (49.7908, 40.7738, -1.4859)
  line L1477 (49.7908, 40.7738, -1.4859) -> (49.7908, 43.7738, -1.4859)
  line L1478 (49.7908, 43.7738, -1.4859) -> (52.2408, 43.7738, -1.4859)
  line L1479 (52.2408, 43.7738, -1.4859) -> (52.2408, 40.7738, -1.4859)
  line L1480 (87.1658, 40.7738, -1.4859) -> (84.7158, 40.7738, -1.4859)
  line L1481 (84.7158, 40.7738, -1.4859) -> (84.7158, 43.7738, -1.4859)
  line L1482 (84.7158, 43.7738, -1.4859) -> (87.1658, 43.7738, -1.4859)
  line L1483 (87.1658, 43.7738, -1.4859) -> (87.1658, 40.7738, -1.4859)
  line L1484 (122.0908, 40.7738, -1.4859) -> (119.6408, 40.7738, -1.4859)
  line L1485 (119.6408, 40.7738, -1.4859) -> (119.6408, 43.7738, -1.4859)
  line L1486 (119.6408, 43.7738, -1.4859) -> (122.0908, 43.7738, -1.4859)
  line L1487 (122.0908, 43.7738, -1.4859) -> (122.0908, 40.7738, -1.4859)
  line L1488 (13.8368, 43.74, -1.4859) -> (14.0196, 43.6806, -1.4859)
  line L1489 (14.0196, 43.6806, -1.4859) -> (14.1909, 43.5933, -1.4859)
  line L1490 (14.1909, 43.5933, -1.4859) -> (14.3464, 43.4803, -1.4859)
  line L1491 (14.3464, 43.4803, -1.4859) -> (14.4823, 43.3444, -1.4859)
  line L1492 (14.4823, 43.3444, -1.4859) -> (14.5953, 43.1889, -1.4859)
  line L1493 (14.5953, 43.1889, -1.4859) -> (14.6826, 43.0176, -1.4859)
  line L1494 (14.6826, 43.0176, -1.4859) -> (14.742, 42.8348, -1.4859)
  line L1495 (14.742, 42.8348, -1.4859) -> (14.772, 42.6449, -1.4859)
  line L1496 (14.772, 42.6449, -1.4859) -> (14.7758, 42.5488, -1.4859)
  line L1497 (14.7758, 42.5488, -1.4859) -> (14.7758, 41.9988, -1.4859)
  line L1498 (14.7758, 41.9988, -1.4859) -> (14.772, 41.9027, -1.4859)
  line L1499 (14.772, 41.9027, -1.4859) -> (14.742, 41.7129, -1.4859)
  line L1500 (14.742, 41.7129, -1.4859) -> (14.6826, 41.53, -1.4859)
  line L1501 (14.6826, 41.53, -1.4859) -> (14.5953, 41.3588, -1.4859)
  line L1502 (14.5953, 41.3588, -1.4859) -> (14.4823, 41.2033, -1.4859)
  line L1503 (14.4823, 41.2033, -1.4859) -> (14.3464, 41.0673, -1.4859)
  line L1504 (14.3464, 41.0673, -1.4859) -> (14.1909, 40.9544, -1.4859)
  line L1505 (14.1909, 40.9544, -1.4859) -> (14.0196, 40.8671, -1.4859)
  line L1506 (14.0196, 40.8671, -1.4859) -> (13.8368, 40.8077, -1.4859)
  line L1507 (13.8368, 40.8077, -1.4859) -> (13.6469, 40.7776, -1.4859)
  line L1508 (13.6469, 40.7776, -1.4859) -> (13.4547, 40.7776, -1.4859)
  line L1509 (13.4547, 40.7776, -1.4859) -> (13.2648, 40.8077, -1.4859)
  line L1510 (13.2648, 40.8077, -1.4859) -> (13.082, 40.8671, -1.4859)
  line L1511 (13.082, 40.8671, -1.4859) -> (12.9107, 40.9544, -1.4859)
  line L1512 (12.9107, 40.9544, -1.4859) -> (12.7552, 41.0673, -1.4859)
  line L1513 (12.7552, 41.0673, -1.4859) -> (12.6193, 41.2033, -1.4859)
  line L1514 (12.6193, 41.2033, -1.4859) -> (12.5063, 41.3588, -1.4859)
  line L1515 (12.5063, 41.3588, -1.4859) -> (12.419, 41.53, -1.4859)
  line L1516 (12.419, 41.53, -1.4859) -> (12.3596, 41.7129, -1.4859)
  line L1517 (12.3596, 41.7129, -1.4859) -> (12.3296, 41.9027, -1.4859)
  line L1518 (12.3296, 41.9027, -1.4859) -> (12.3258, 41.9988, -1.4859)
  line L1519 (12.3258, 41.9988, -1.4859) -> (12.3258, 42.5488, -1.4859)
  line L1520 (12.3258, 42.5488, -1.4859) -> (12.3296, 42.6449, -1.4859)
  line L1521 (12.3296, 42.6449, -1.4859) -> (12.3596, 42.8348, -1.4859)
  line L1522 (12.3596, 42.8348, -1.4859) -> (12.419, 43.0176, -1.4859)
  line L1523 (12.419, 43.0176, -1.4859) -> (12.5063, 43.1889, -1.4859)
  line L1524 (12.5063, 43.1889, -1.4859) -> (12.6193, 43.3444, -1.4859)
  line L1525 (12.6193, 43.3444, -1.4859) -> (12.7552, 43.4803, -1.4859)
  line L1526 (12.7552, 43.4803, -1.4859) -> (12.9107, 43.5933, -1.4859)
  line L1527 (12.9107, 43.5933, -1.4859) -> (13.082, 43.6806, -1.4859)
  line L1528 (13.082, 43.6806, -1.4859) -> (13.2648, 43.74, -1.4859)
  line L1529 (13.2648, 43.74, -1.4859) -> (13.4547, 43.7701, -1.4859)
  line L1530 (13.4547, 43.7701, -1.4859) -> (13.6469, 43.7701, -1.4859)
  line L1531 (13.6469, 43.7701, -1.4859) -> (13.8368, 43.74, -1.4859)
  line L1532 (48.7618, 43.74, -1.4859) -> (48.9446, 43.6806, -1.4859)
  line L1533 (48.9446, 43.6806, -1.4859) -> (49.1159, 43.5933, -1.4859)
  line L1534 (49.1159, 43.5933, -1.4859) -> (49.2714, 43.4803, -1.4859)
  line L1535 (49.2714, 43.4803, -1.4859) -> (49.4073, 43.3444, -1.4859)
  line L1536 (49.4073, 43.3444, -1.4859) -> (49.5203, 43.1889, -1.4859)
  line L1537 (49.5203, 43.1889, -1.4859) -> (49.6076, 43.0176, -1.4859)
  line L1538 (49.6076, 43.0176, -1.4859) -> (49.667, 42.8348, -1.4859)
  line L1539 (49.667, 42.8348, -1.4859) -> (49.697, 42.6449, -1.4859)
  line L1540 (49.697, 42.6449, -1.4859) -> (49.7008, 42.5488, -1.4859)
  line L1541 (49.7008, 42.5488, -1.4859) -> (49.7008, 41.9988, -1.4859)
  line L1542 (49.7008, 41.9988, -1.4859) -> (49.697, 41.9027, -1.4859)
  line L1543 (49.697, 41.9027, -1.4859) -> (49.667, 41.7129, -1.4859)
  line L1544 (49.667, 41.7129, -1.4859) -> (49.6076, 41.53, -1.4859)
  line L1545 (49.6076, 41.53, -1.4859) -> (49.5203, 41.3588, -1.4859)
  line L1546 (49.5203, 41.3588, -1.4859) -> (49.4073, 41.2033, -1.4859)
  line L1547 (49.4073, 41.2033, -1.4859) -> (49.2714, 41.0673, -1.4859)
  line L1548 (49.2714, 41.0673, -1.4859) -> (49.1159, 40.9544, -1.4859)
  line L1549 (49.1159, 40.9544, -1.4859) -> (48.9446, 40.8671, -1.4859)
  line L1550 (48.9446, 40.8671, -1.4859) -> (48.7618, 40.8077, -1.4859)
  line L1551 (48.7618, 40.8077, -1.4859) -> (48.5719, 40.7776, -1.4859)
  line L1552 (48.5719, 40.7776, -1.4859) -> (48.3797, 40.7776, -1.4859)
  line L1553 (48.3797, 40.7776, -1.4859) -> (48.1898, 40.8077, -1.4859)
  line L1554 (48.1898, 40.8077, -1.4859) -> (48.007, 40.8671, -1.4859)
  line L1555 (48.007, 40.8671, -1.4859) -> (47.8357, 40.9544, -1.4859)
  line L1556 (47.8357, 40.9544, -1.4859) -> (47.6802, 41.0673, -1.4859)
  line L1557 (47.6802, 41.0673, -1.4859) -> (47.5443, 41.2033, -1.4859)
  line L1558 (47.5443, 41.2033, -1.4859) -> (47.4313, 41.3588, -1.4859)
  line L1559 (47.4313, 41.3588, -1.4859) -> (47.344, 41.53, -1.4859)
  line L1560 (47.344, 41.53, -1.4859) -> (47.2846, 41.7129, -1.4859)
  line L1561 (47.2846, 41.7129, -1.4859) -> (47.2546, 41.9027, -1.4859)
  line L1562 (47.2546, 41.9027, -1.4859) -> (47.2508, 41.9988, -1.4859)
  line L1563 (47.2508, 41.9988, -1.4859) -> (47.2508, 42.5488, -1.4859)
  line L1564 (47.2508, 42.5488, -1.4859) -> (47.2546, 42.6449, -1.4859)
  line L1565 (47.2546, 42.6449, -1.4859) -> (47.2846, 42.8348, -1.4859)
  line L1566 (47.2846, 42.8348, -1.4859) -> (47.344, 43.0176, -1.4859)
  line L1567 (47.344, 43.0176, -1.4859) -> (47.4313, 43.1889, -1.4859)
  line L1568 (47.4313, 43.1889, -1.4859) -> (47.5443, 43.3444, -1.4859)
  line L1569 (47.5443, 43.3444, -1.4859) -> (47.6802, 43.4803, -1.4859)
  line L1570 (47.6802, 43.4803, -1.4859) -> (47.8357, 43.5933, -1.4859)
  line L1571 (47.8357, 43.5933, -1.4859) -> (48.007, 43.6806, -1.4859)
  line L1572 (48.007, 43.6806, -1.4859) -> (48.1898, 43.74, -1.4859)
  line L1573 (48.1898, 43.74, -1.4859) -> (48.3797, 43.7701, -1.4859)
  line L1574 (48.3797, 43.7701, -1.4859) -> (48.5719, 43.7701, -1.4859)
  line L1575 (48.5719, 43.7701, -1.4859) -> (48.7618, 43.74, -1.4859)
  line L1576 (83.6868, 43.74, -1.4859) -> (83.8696, 43.6806, -1.4859)
  line L1577 (83.8696, 43.6806, -1.4859) -> (84.0409, 43.5933, -1.4859)
  line L1578 (84.0409, 43.5933, -1.4859) -> (84.1964, 43.4803, -1.4859)
  line L1579 (84.1964, 43.4803, -1.4859) -> (84.3323, 43.3444, -1.4859)
  line L1580 (84.3323, 43.3444, -1.4859) -> (84.4453, 43.1889, -1.4859)
  line L1581 (84.4453, 43.1889, -1.4859) -> (84.5326, 43.0176, -1.4859)
  line L1582 (84.5326, 43.0176, -1.4859) -> (84.592, 42.8348, -1.4859)
  line L1583 (84.592, 42.8348, -1.4859) -> (84.622, 42.6449, -1.4859)
  line L1584 (84.622, 42.6449, -1.4859) -> (84.6258, 42.5488, -1.4859)
  line L1585 (84.6258, 42.5488, -1.4859) -> (84.6258, 41.9988, -1.4859)
  line L1586 (84.6258, 41.9988, -1.4859) -> (84.622, 41.9027, -1.4859)
  line L1587 (84.622, 41.9027, -1.4859) -> (84.592, 41.7129, -1.4859)
  line L1588 (84.592, 41.7129, -1.4859) -> (84.5326, 41.53, -1.4859)
  line L1589 (84.5326, 41.53, -1.4859) -> (84.4453, 41.3588, -1.4859)
  line L1590 (84.4453, 41.3588, -1.4859) -> (84.3323, 41.2033, -1.4859)
  line L1591 (84.3323, 41.2033, -1.4859) -> (84.1964, 41.0673, -1.4859)
  line L1592 (84.1964, 41.0673, -1.4859) -> (84.0409, 40.9544, -1.4859)
  line L1593 (84.0409, 40.9544, -1.4859) -> (83.8696, 40.8671, -1.4859)
  line L1594 (83.8696, 40.8671, -1.4859) -> (83.6868, 40.8077, -1.4859)
  line L1595 (83.6868, 40.8077, -1.4859) -> (83.4969, 40.7776, -1.4859)
  line L1596 (83.4969, 40.7776, -1.4859) -> (83.3047, 40.7776, -1.4859)
  line L1597 (83.3047, 40.7776, -1.4859) -> (83.1148, 40.8077, -1.4859)
  line L1598 (83.1148, 40.8077, -1.4859) -> (82.932, 40.8671, -1.4859)
  line L1599 (82.932, 40.8671, -1.4859) -> (82.7607, 40.9544, -1.4859)
  line L1600 (82.7607, 40.9544, -1.4859) -> (82.6052, 41.0673, -1.4859)
  line L1601 (82.6052, 41.0673, -1.4859) -> (82.4693, 41.2033, -1.4859)
  line L1602 (82.4693, 41.2033, -1.4859) -> (82.3563, 41.3588, -1.4859)
  line L1603 (82.3563, 41.3588, -1.4859) -> (82.269, 41.53, -1.4859)
  line L1604 (82.269, 41.53, -1.4859) -> (82.2096, 41.7129, -1.4859)
  line L1605 (82.2096, 41.7129, -1.4859) -> (82.1796, 41.9027, -1.4859)
  line L1606 (82.1796, 41.9027, -1.4859) -> (82.1758, 41.9988, -1.4859)
  line L1607 (82.1758, 41.9988, -1.4859) -> (82.1758, 42.5488, -1.4859)
  line L1608 (82.1758, 42.5488, -1.4859) -> (82.1796, 42.6449, -1.4859)
  line L1609 (82.1796, 42.6449, -1.4859) -> (82.2096, 42.8348, -1.4859)
  line L1610 (82.2096, 42.8348, -1.4859) -> (82.269, 43.0176, -1.4859)
  line L1611 (82.269, 43.0176, -1.4859) -> (82.3563, 43.1889, -1.4859)
  line L1612 (82.3563, 43.1889, -1.4859) -> (82.4693, 43.3444, -1.4859)
  line L1613 (82.4693, 43.3444, -1.4859) -> (82.6052, 43.4803, -1.4859)
  line L1614 (82.6052, 43.4803, -1.4859) -> (82.7607, 43.5933, -1.4859)
  line L1615 (82.7607, 43.5933, -1.4859) -> (82.932, 43.6806, -1.4859)
  line L1616 (82.932, 43.6806, -1.4859) -> (83.1148, 43.74, -1.4859)
  line L1617 (83.1148, 43.74, -1.4859) -> (83.3047, 43.7701, -1.4859)
  line L1618 (83.3047, 43.7701, -1.4859) -> (83.4969, 43.7701, -1.4859)
  line L1619 (83.4969, 43.7701, -1.4859) -> (83.6868, 43.74, -1.4859)
  line L1620 (118.6118, 43.74, -1.4859) -> (118.7946, 43.6806, -1.4859)
  line L1621 (118.7946, 43.6806, -1.4859) -> (118.9659, 43.5933, -1.4859)
  line L1622 (118.9659, 43.5933, -1.4859) -> (119.1214, 43.4803, -1.4859)
  line L1623 (119.1214, 43.4803, -1.4859) -> (119.2573, 43.3444, -1.4859)
  line L1624 (119.2573, 43.3444, -1.4859) -> (119.3703, 43.1889, -1.4859)
  line L1625 (119.3703, 43.1889, -1.4859) -> (119.4576, 43.0176, -1.4859)
  line L1626 (119.4576, 43.0176, -1.4859) -> (119.517, 42.8348, -1.4859)
  line L1627 (119.517, 42.8348, -1.4859) -> (119.547, 42.6449, -1.4859)
  line L1628 (119.547, 42.6449, -1.4859) -> (119.5508, 42.5488, -1.4859)
  line L1629 (119.5508, 42.5488, -1.4859) -> (119.5508, 41.9988, -1.4859)
  line L1630 (119.5508, 41.9988, -1.4859) -> (119.547, 41.9027, -1.4859)
  line L1631 (119.547, 41.9027, -1.4859) -> (119.517, 41.7129, -1.4859)
  line L1632 (119.517, 41.7129, -1.4859) -> (119.4576, 41.53, -1.4859)
  line L1633 (119.4576, 41.53, -1.4859) -> (119.3703, 41.3588, -1.4859)
  line L1634 (119.3703, 41.3588, -1.4859) -> (119.2573, 41.2033, -1.4859)
  line L1635 (119.2573, 41.2033, -1.4859) -> (119.1214, 41.0673, -1.4859)
  line L1636 (119.1214, 41.0673, -1.4859) -> (118.9659, 40.9544, -1.4859)
  line L1637 (118.9659, 40.9544, -1.4859) -> (118.7946, 40.8671, -1.4859)
  line L1638 (118.7946, 40.8671, -1.4859) -> (118.6118, 40.8077, -1.4859)
  line L1639 (118.6118, 40.8077, -1.4859) -> (118.4219, 40.7776, -1.4859)
  line L1640 (118.4219, 40.7776, -1.4859) -> (118.2297, 40.7776, -1.4859)
  line L1641 (118.2297, 40.7776, -1.4859) -> (118.0398, 40.8077, -1.4859)
  line L1642 (118.0398, 40.8077, -1.4859) -> (117.857, 40.8671, -1.4859)
  line L1643 (117.857, 40.8671, -1.4859) -> (117.6857, 40.9544, -1.4859)
  line L1644 (117.6857, 40.9544, -1.4859) -> (117.5302, 41.0673, -1.4859)
  line L1645 (117.5302, 41.0673, -1.4859) -> (117.3943, 41.2033, -1.4859)
  line L1646 (117.3943, 41.2033, -1.4859) -> (117.2813, 41.3588, -1.4859)
  line L1647 (117.2813, 41.3588, -1.4859) -> (117.194, 41.53, -1.4859)
  line L1648 (117.194, 41.53, -1.4859) -> (117.1346, 41.7129, -1.4859)
  line L1649 (117.1346, 41.7129, -1.4859) -> (117.1046, 41.9027, -1.4859)
  line L1650 (117.1046, 41.9027, -1.4859) -> (117.1008, 41.9988, -1.4859)
  line L1651 (117.1008, 41.9988, -1.4859) -> (117.1008, 42.5488, -1.4859)
  line L1652 (117.1008, 42.5488, -1.4859) -> (117.1046, 42.6449, -1.4859)
  line L1653 (117.1046, 42.6449, -1.4859) -> (117.1346, 42.8348, -1.4859)
  line L1654 (117.1346, 42.8348, -1.4859) -> (117.194, 43.0176, -1.4859)
  line L1655 (117.194, 43.0176, -1.4859) -> (117.2813, 43.1889, -1.4859)
  line L1656 (117.2813, 43.1889, -1.4859) -> (117.3943, 43.3444, -1.4859)
  line L1657 (117.3943, 43.3444, -1.4859) -> (117.5302, 43.4803, -1.4859)
  line L1658 (117.5302, 43.4803, -1.4859) -> (117.6857, 43.5933, -1.4859)
  line L1659 (117.6857, 43.5933, -1.4859) -> (117.857, 43.6806, -1.4859)
  line L1660 (117.857, 43.6806, -1.4859) -> (118.0398, 43.74, -1.4859)
  line L1661 (118.0398, 43.74, -1.4859) -> (118.2297, 43.7701, -1.4859)
  line L1662 (118.2297, 43.7701, -1.4859) -> (118.4219, 43.7701, -1.4859)
  line L1663 (118.4219, 43.7701, -1.4859) -> (118.6118, 43.74, -1.4859)
  line L1664 (25.7814, 54.7991, -1.4859) -> (25.8946, 54.7437, -1.4859)
  line L1665 (25.8946, 54.7437, -1.4859) -> (25.9837, 54.6546, -1.4859)
  line L1666 (25.9837, 54.6546, -1.4859) -> (26.0391, 54.5414, -1.4859)
  line L1667 (26.0391, 54.5414, -1.4859) -> (26.055, 54.4322, -1.4859)
  line L1668 (26.055, 54.4322, -1.4859) -> (26.055, 52.1978, -1.4859)
  line L1669 (26.055, 52.1978, -1.4859) -> (26.0391, 52.0886, -1.4859)
  line L1670 (26.0391, 52.0886, -1.4859) -> (25.9837, 51.9754, -1.4859)
  line L1671 (25.9837, 51.9754, -1.4859) -> (25.8946, 51.8863, -1.4859)
  line L1672 (25.8946, 51.8863, -1.4859) -> (25.7814, 51.8309, -1.4859)
  line L1673 (25.7814, 51.8309, -1.4859) -> (25.6722, 51.815, -1.4859)
  line L1674 (25.6722, 51.815, -1.4859) -> (23.9878, 51.815, -1.4859)
  line L1675 (23.9878, 51.815, -1.4859) -> (23.8786, 51.8309, -1.4859)
  line L1676 (23.8786, 51.8309, -1.4859) -> (23.7654, 51.8863, -1.4859)
  line L1677 (23.7654, 51.8863, -1.4859) -> (23.6763, 51.9754, -1.4859)
  line L1678 (23.6763, 51.9754, -1.4859) -> (23.6209, 52.0886, -1.4859)
  line L1679 (23.6209, 52.0886, -1.4859) -> (23.605, 52.1978, -1.4859)